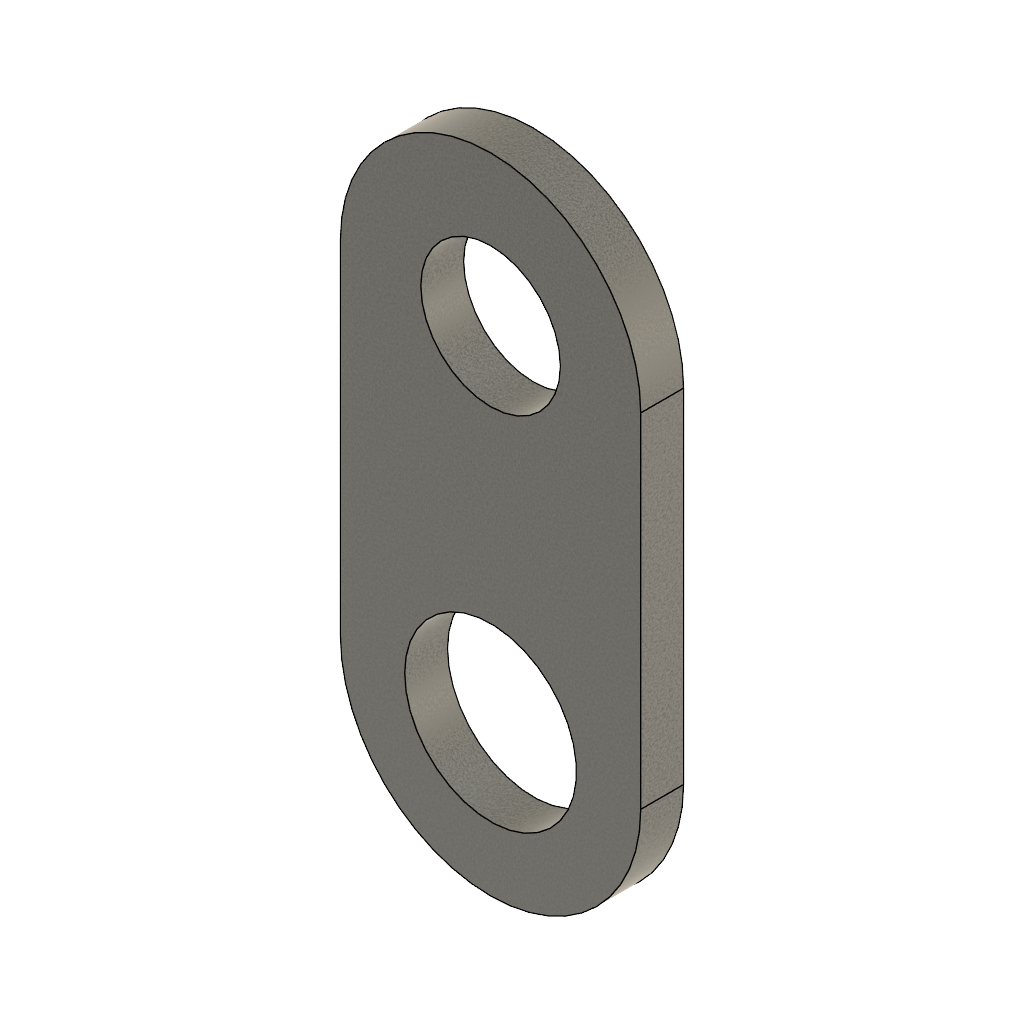
A6-FEA-Design1_Link (Autodesk Fusion 360 design; units mm, degrees)
part number: 2026-10-21-17-00-39-858
part number: 2026-10-21-17-00-39-859
Autodesk Fusion 360 part; units mm, degrees
sketch "Sketch1" plane through (0, 0, 0) normal (0, 1, 0) x (1, 0, 0)
  line L0 (-22.225, 0) -> (-22.225, -50.8)
  arc A0 (-22.225, -50.8) -> (22.225, -50.8) centre (0, -50.8) ccw
  line L1 (22.225, -50.8) -> (22.225, 0)
  arc A1 (22.225, 0) -> (-22.225, 0) centre (0, 0) ccw
  line L2 (0, 0) -> (0, -50.8) construction
  dimension "d54" = 50.8
  dimension "d55" = 44.45
  constraint tangent L0 A0
  constraint tangent A0 L1
  constraint parallel L0 L1
  constraint tangent L1 A1
  constraint tangent L0 A1
  constraint vertical L2
  constraint coincident A1.centre L2.start
  measures "d54" distance of A1.centre A0.centre
  measures "d55" distance of L0 L1
extrude "Extrude1" add sketch "Sketch1" along normal blind 6.35
sketch "Sketch2" plane through (0, 0, 0) normal (0, -1, 0) x (1, 0, 0)
  arc A0 (-22.225, 0) -> (22.225, 0) centre (0, 0) ccw
  line L0 (22.225, 0) -> (22.225, 50.8)
  arc A1 (22.225, 50.8) -> (-22.225, 50.8) centre (0, 50.8) ccw
  line L1 (-22.225, 50.8) -> (-22.225, 0)
  circle A2 centre (0, 50.8) radius 10.3187
  circle A3 centre (0, 0) radius 12.7
  dimension "d58" = 20.6375
  dimension "d59" = 25.4
  constraint concentric A1 A2
  constraint coincident A0.centre A3.centre
  measures "d58" diameter of A2
  measures "d59" diameter of A3
extrude "Extrude2" cut sketch "Sketch2" against normal blind 6.35 contours A2 | A3
component "Component" placed x (1, 0, 0) y (0, 1, 0) z (0, 0, 1) at (0, 0, 0)
equation "d54 = link_spacing"
equation "d55 = link_width"
equation "d56 = link_thickness"
equation "d58 = link_a_hole"
equation "d59 = link_shaft_hole"
equation "d60 = -link_thickness"
equation "a_diameter = 0.8125 in"
equation "link_width = 1.750 in"
equation "link_thickness = 0.250 in"
equation "link_spacing = 2.000 in"
equation "link_a_hole = a_diameter"
equation "shaft_basic_diameter = 1.000 in"
equation "link_shaft_hole = shaft_basic_diameter"
